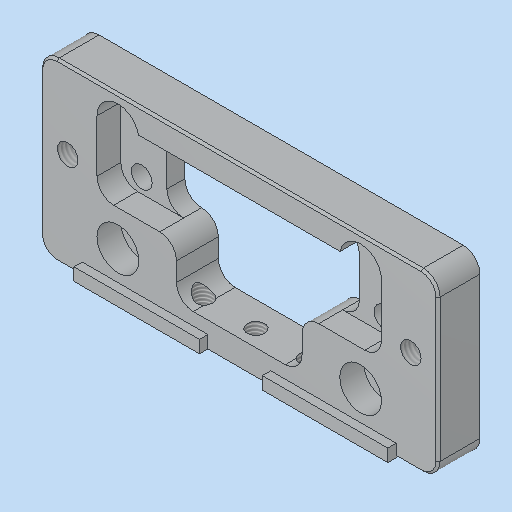
# Autodesk Inventor part: MM0948AN002_G01_106
Saved by Autodesk Inventor 2023.3 (Build 273359000, 359)
## iProperties
RuleStatus: InUse
Created: 2023-03-23
Part Number: MM0948AN002_G01_106
Material: 3.3547 AlMg4,5Mn0,7 - AW 5083
Description: =<RBPARTNOTITLE2>
Document SubType Name: Modeling
Designer: ric7an
Mass: 64.1559 g
Surface Area: 111.165 cm^2
Volume: 23.7615 cm^3
Density: 2.7 g/cm^3
Appearance: Aluminium AnP
AnP_Kategorie: 1
AnP_Material: =<Material>
MaxAbmaße: 26 x 50 x 120 (FM)
AnP_TemplVers: 20200821
RBDOCUMENTTYPE: DRF
RBDOCUMENTVERSION: 00
RBDRAWINGMAINSCALE: 1:1
RBDRAWINGMISSINGSPEC: --
RBDRAWINGVOLUME: --
RBDSV1: 0850
RBGBEDGESIN1: +0,5
RBGBEDGESIN2: +0,2
RBGBEDGESOUT1: -0,3
RBGBEDGESOUT2: -0,1
RBMATERIAL: =<Material>
RBMATMEETS: --
RBMATNO: =<Part Number>
RBPARTMADEOF: 26 x 50 x 120 (FM)
RBPARTNO: SIEHE MNR
RBPARTNOTITLE1: manufactured part
RBPARTNOTITLE2: Anfertigungsteil
RBPARTSAFETYINDICATOR: --
RBSURFACE: anodised colourless
RBSURFACE2: eloxiert farblos
RBZEDGESNORM: ISO13715:2002-06
RBZGENDIMCLASS: m
RBZGENDIMNORM: ISO 2768-1:1989-11
RBZGENGEOCLASS: H
RBZGENGEONORM: ISO 2768-2:1989-11
RBZSURFACENORM: ISO13D2:2002-02
RBZTOLERANCENORM: ISO 14405-1:2010-12
AnP_Kommentar_aktuell: =<Comments>
AnP_Material_aktuell: =<Material>
Author: FH/Wi
Keywords: =<RBPARTMADEOF>
Comments: =<RBSURFACE2>
Revision Number: 01
Autodesk Inventor part; units mm, degrees
ref_plane "YZ Plane" through (0, 0, 0) normal (1, 0, 0) x (0, 1, 0)
ref_plane "XZ Plane" through (0, 0, 0) normal (0, 1, 0) x (-1, 0, 0)
ref_plane "XY Plane" through (0, 0, 0) normal (0, 0, 1) x (1, 0, 0)
sketch "Skizze1" plane through (0, 0, 0) normal (0, 0, 1) x (1, 0, 0)
  line L0 (-47.5, 42) -> (47.5, 42)
  line L1 (47.5, 42) -> (47.5, 0)
  line L2 (47.5, 0) -> (-47.5, 0)
  line L3 (-47.5, 0) -> (-47.5, 42)
  line L4 (0, 50.4) -> (0, -8.4) projected
  line L5 (-66.5, 0) -> (66.5, 0) projected
  point P0 (0, 0)
  dimension "d0" = 42
  dimension "d1" = 95
  constraints: 8 end point, 2 parallel, 1 collinear, 1 horizontal, 1 perpendicular, 1 other
  measures "d0" distance of L0.end L1.end
  measures "d1" distance of L0.start L0.end
extrude "Extrusion1" add sketch "Skizze1" against normal blind 10
sketch "Skizze2" plane through (0, 0, 0) normal (0, 0, 1) x (1, 0, 0)
  line L0 (-47.5, 42) -> (-47.5, 0) projected
  line L1 (-47.5, 0) -> (47.5, 0) projected
  line L2 (47.5, 0) -> (47.5, 42) projected
  line L3 (47.5, 42) -> (-47.5, 42) projected
  line L4 (-47.5, 0) -> (47.5, 0)
  line L5 (47.5, 0) -> (47.5, 3)
  line L6 (47.5, 3) -> (-47.5, 3)
  line L7 (-47.5, 3) -> (-47.5, 0)
  line L8 (-7.5, 3) -> (7.5, 3)
  line L9 (7.5, 3) -> (7.5, 0)
  line L10 (7.5, 0) -> (-7.5, 0)
  line L11 (-7.5, 0) -> (-7.5, 3)
  line L12 (0, 50.4) -> (0, -8.4) projected
  line L13 (-47.5, 3) -> (-37.5, 3)
  line L14 (-37.5, 3) -> (-37.5, 0)
  line L15 (-37.5, 0) -> (-47.5, 0)
  line L16 (-47.5, 0) -> (-47.5, 3)
  line L17 (47.5, 3) -> (37.5, 3)
  line L18 (37.5, 3) -> (37.5, 0)
  line L19 (37.5, 0) -> (47.5, 0)
  line L20 (47.5, 0) -> (47.5, 3)
  point P0 (0, 0)
  point P1 (7.5, 0)
  point P2 (-37.5, 3)
  point P3 (-37.5, 0)
  point P4 (37.5, 0)
  point P5 (37.5, 3)
  dimension "d4" = 3
  dimension "d48" = 15
  dimension "d61" = 10
  constraints: 32 end point, 8 parallel, 5 point on line, 4 horizontal, 4 perpendicular, 2 other
  measures "d4" distance between parallel lines of L1 L6
  measures "d48" distance between parallel lines of L9 L11
  measures "d61" distance between parallel lines of L2 L18
extrude "Extrusion2" add sketch "Skizze2" along normal blind 2 contours L6 L11 L1 L14 | L6 L18 L1 L9
sketch "Skizze7" plane through (0, 0, 0) normal (0, 0, 1) x (1, 0, 0)
  line L0 (0, 50.4) -> (0, -8.4) projected
  line L1 (-37.5, 0) -> (-7.5, 0) projected
  point P0 (0, 0)
  point P1 (-41, 23.5)
  point P2 (41, 23.5)
  point P3 (-59, 0)
  point P4 (59, 0)
  dimension "d39" = 82
  dimension "d40" = 23.5
  constraints: 1 symmetric about line
  measures "d39" distance of point (41, 23.5) point (-41, 23.5)
  measures "d40" distance from line of L1 point (41, 23.5)
hole "Bohrung4" at (-41, 23.5, 0) at (41, 23.5, 0) direction (0, 0, -1) diameter 4.917 end through all thread size "M6x1" designation "M6" class "6H" standard "ISO Metric profile"
fillet "Rundung1" radius 4 4 edges at (-47.5, 42, -5) (47.5, 42, -5) (-47.5, 0, -5) (47.5, 0, -5)
sketch "Skizze10" plane through (-7.5, 0, 0) normal (0, -1, 0) x (1, 0, 0)
  line L0 (7.5, 6.2) -> (7.5, -23.2) projected
  line L1 (0, 0) -> (15, 0) projected
  point P0 (7.5, 0)
  point P1 (-5, -4)
  point P2 (-27.5, -4)
  point P3 (42.5, -4)
  point P4 (20, -4)
  point P5 (7.5, -4)
  point P6 (7.5, -19)
  dimension "d77" = 70
  dimension "d78" = 25
  dimension "d79" = 4
  dimension "d97" = 15
  constraints: 2 horizontal alignment, 2 point on line, 2 symmetric about line
  measures "d77" distance of point (42.5, -4) point (-27.5, -4)
  measures "d78" distance of point (20, -4) point (-5, -4)
  measures "d79" distance from line of L1 point (20, -4)
  measures "d97" vertical distance of point (7.5, -19) point (-27.5, -4)
hole "Bohrung5" at (-12.5, 0, -4) at (12.5, 0, -4) at (0, 0, -4) at (0, 0, -19) direction (0, 1, 0) diameter 4.134 depth 14.2 tip angle 118 thread size "M5x0.8" designation "M5" class "6H" standard "ISO Metric profile"
chamfer "Fase2" distance 0.5 angle 45 9 edges at (0, 42, 0) (-46.3284, 40.8284, 0) (-47.5, 21, 0) (-46.3284, 1.1716, 0) (-40.5, 0, 0) (46.3284, 40.8284, 0) (47.5, 21, 0) (46.3284, 1.1716, 0) (40.5, 0, 0)
sketch "Skizze16" plane through (0, 0, 0) normal (0, 0, 1) x (1, 0, 0)
  line L0 (0, 50.4) -> (0, -8.4) projected
  line L1 (-7.5, 0) -> (-37.5, 0) projected
  point P0 (0, 0)
  point P1 (-29, 35)
  point P2 (-29, 10)
  point P3 (29, 35)
  point P4 (29, 10)
  point P5 (-49.5, 0)
  dimension "d135" = 58
  dimension "d136" = 10
  dimension "d137" = 25
  constraints: 2 symmetric about line, 1 vertical alignment
  measures "d135" distance of point (29, 10) point (-29, 10)
  measures "d136" distance from line of point (-29, 10) L1
  measures "d137" distance of point (-29, 10) point (-29, 35)
hole "Bohrung9" at (-29, 35, 0) at (-29, 10, 0) at (29, 35, 0) at (29, 10, 0) direction (0, 0, -1) diameter 5.5 end through all counterbore diameter 10 counterbore depth 5.7 clearance for "Inbusschraube ISO 4762  versenkt" size "M5" standard "ISO"
sketch "Skizze17" plane through (0, 0, -10) normal (0, 0, -1) x (-1, 0, 0)
  circle A0 centre (-29, 35) radius 2.75 projected
  circle A1 centre (29, 35) radius 2.75 projected
  line L0 (-43.5, 0) -> (43.5, 0) projected
  point P0 (0, 0)
  point P1 (-29, 22)
  point P2 (29, 22)
  dimension "d163" = 22
  constraints: 2 vertical alignment, 1 horizontal alignment
  measures "d163" distance from line of L0 point (-29, 22)
hole "Bohrung10" at (29, 22, -10) at (-29, 22, -10) direction (0, 0, 1) diameter 4.8 end through all counterbore diameter 5 counterbore depth 10
sketch "Skizze18" plane through (0, 0, 0) normal (0, 0, 1) x (1, 0, 0)
  line L0 (-23, 36) -> (23, 36)
  line L1 (23, 36) -> (23, 6)
  line L2 (23, 6) -> (-23, 6)
  line L3 (-23, 6) -> (-23, 36)
  line L4 (0, 50.4) -> (0, -8.4) projected
  line L5 (43.5, 42) -> (-43.5, 42) projected
  line L6 (-7.5, 0) -> (7.5, 0) projected
  line L7 (-23, 18.5) -> (-15, 18.5)
  line L8 (-15, 18.5) -> (-15, 6)
  line L9 (-15, 6) -> (-23, 6)
  line L10 (-23, 6) -> (-23, 18.5)
  line L11 (23, 18.5) -> (15, 18.5)
  line L12 (15, 18.5) -> (15, 6)
  line L13 (15, 6) -> (23, 6)
  line L14 (23, 6) -> (23, 18.5)
  point P0 (0, 0)
  dimension "d153" = 6
  dimension "d154" = 6
  dimension "d155" = 46
  dimension "d161" = 12.5
  dimension "d165" = 15
  constraints: 24 end point, 6 parallel, 4 point on line, 3 horizontal, 3 perpendicular, 1 collinear, 2 other
  measures "d153" distance between parallel lines of L5 L0
  measures "d154" distance between parallel lines of L6 L2
  measures "d155" distance between parallel lines of L1 L3
  measures "d161" distance of L7.end L8.end
  measures "d165" distance between parallel lines of L4 L8
extrude "Extrusion8" cut sketch "Skizze18" against normal through all contours L0 L4 L2 L8 L7 L3 | L0 L1 L11 L12 L2 L4
fillet "Rundung6" radius 4 8 edges at (-23, 18.5, -5) (-15, 18.5, -5) (-15, 6, -5) (15, 6, -5) (15, 18.5, -5) (23, 18.5, -5) (23, 36, -5) (-23, 36, -5)
sketch "Skizze20" plane through (0, 0, 0) normal (0, 0, 1) x (1, 0, 0)
  line L0 (-19, 36) -> (19, 36) projected
  line L1 (-34, 36) -> (34, 36)
  line L2 (34, 36) -> (34, 18.5)
  line L3 (34, 18.5) -> (-34, 18.5)
  line L4 (-34, 18.5) -> (-34, 36)
  line L5 (0, 50.4) -> (0, -8.4) projected
  line L6 (-66.5, 0) -> (66.5, 0) projected
  circle A0 centre (-29, 35) radius 5 projected
  circle A1 centre (29, 35) radius 5 projected
  point P0 (0, 0)
  point P1 (-19, 18.5)
  point P2 (19, 18.5)
  point P3 (34, 35)
  point P4 (33.899, 36)
  point P5 (-33.899, 36)
  point P6 (-34, 35)
  constraints: 8 end point, 2 parallel, 1 collinear, 1 horizontal, 1 perpendicular, 1 point on line, 1 tangent, 1 other
extrude "Extrusion10" cut sketch "Skizze20" against normal up to surface (5.7 mm away) contours L0 L5 L3 L4 A0 L1 | L0 L1 A1 L2 L3 L5 | A0 L1 | L1 A1 picked at (-28.0532, 32.0793) picked at (29.2294, 34.0159)
fillet "Rundung7" radius 4 2 edges at (-34, 18.5, -2.85) (34, 18.5, -2.85)
